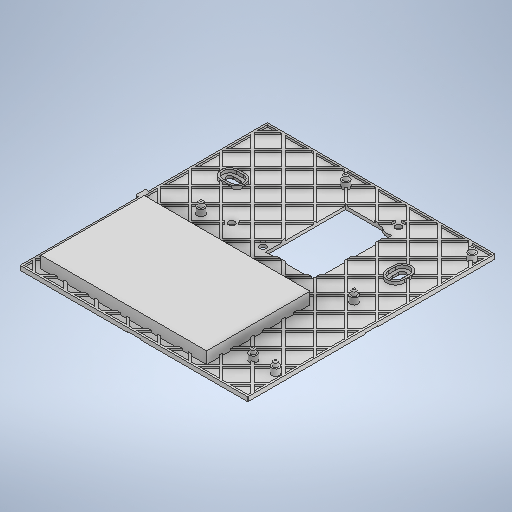
# Autodesk Inventor part: Back
Saved by Autodesk Inventor 2025.2 (Build 292293000, 293)
## iProperties
Created: 2026-06-16
Part Number: Back
Material: Generic
Document SubType Name: Modeling
Designer: Bruno
Density: 1 g/cm^3
Appearance: Default
Author: Bruno
## iProperties of the stored document Back_3DPrint.ipt
Created: 2026-06-25
Part Number: Back_3DPrint
Material: Generic
Document SubType Name: Modeling
Designer: Bruno
Density: 1 g/cm^3
Appearance: Default
Author: Bruno
Autodesk Inventor part; units mm, degrees
(part 1 of 2)
ref_plane "YZ Plane" through (0, 0, 0) normal (1, 0, 0) x (0, 1, 0)
ref_plane "XZ Plane" through (0, 0, 0) normal (0, 1, 0) x (-1, 0, 0)
ref_plane "XY Plane" through (0, 0, 0) normal (0, 0, 1) x (1, 0, 0)
sketch "Sketch1" plane through (0, 0, 0) normal (0, 1, 0) x (-1, 0, 0)
  line L0 (56.075, 35) -> (-60.725, 35) construction
  line L1 (-60.725, 35) -> (-60.725, -33.4)
  line L2 (-60.725, -33.4) -> (56.075, -33.4)
  line L3 (56.075, -33.4) -> (56.075, 35)
  line L4 (56.075, 35) -> (56.075, 93.4)
  line L5 (56.075, 93.4) -> (-60.725, 93.4)
  line L6 (-60.725, 93.4) -> (-60.725, 35)
  line L7 (20.8, 25.375) -> (-25.45, 25.375) construction
  line L8 (-25.45, 25.375) -> (-26.8, 24.025) construction
  line L9 (-26.8, 24.025) -> (-26.8, -24.025) construction
  line L10 (-26.8, -24.025) -> (-25.45, -25.375) construction
  line L11 (-25.45, -25.375) -> (20.8, -25.375) construction
  line L12 (20.8, -25.375) -> (26.8, -19.375) construction
  line L13 (26.8, -19.375) -> (26.8, 19.375) construction
  line L14 (26.8, 19.375) -> (20.8, 25.375) construction
  line L15 (0, 0) -> (14.4314, 0) construction
  line L16 (0, 0) -> (0, -16.3177) construction
  line L17 (20.8414, 25.475) -> (-25.4914, 25.475)
  line L18 (-25.4914, 25.475) -> (-26.9, 24.0664)
  line L19 (-26.9, 24.0664) -> (-26.9, -24.0664)
  line L20 (-26.9, -24.0664) -> (-25.4914, -25.475)
  line L21 (-25.4914, -25.475) -> (20.8414, -25.475)
  line L22 (20.8414, -25.475) -> (26.9, -19.4164)
  line L23 (26.9, -19.4164) -> (26.9, 19.4164) construction
  line L24 (26.9, 19.4164) -> (20.8414, 25.475)
  arc A0 (-26.9, -24.0664) -> (-25.4914, -25.475) centre (-25.4914, -24.0664) ccw
  arc A1 (-25.4914, 25.475) -> (-26.9, 24.0664) centre (-25.4914, 24.0664) ccw
  line L25 (29.5, -16.8716) -> (29.5, 16.8716)
  line L26 (26.9, -19.4164) -> (29.5, -16.8164)
  line L27 (26.9, 19.4164) -> (29.5, 16.8164)
  line L28 (-2.325, 0) -> (-2.325, -9.0577) construction
  line L29 (57.675, 95) -> (57.675, 33.4) construction
  line L30 (57.675, 33.4) -> (57.675, -35) construction
  line L31 (57.675, -35) -> (-62.325, -35) construction
  line L32 (-62.325, -35) -> (-62.325, 33.4) construction
  line L33 (-62.325, 33.4) -> (-62.325, 95) construction
  line L34 (-62.325, 95) -> (57.675, 95) construction
  line L35 (32.3911, 91.5) -> (-28.8133, 91.5) construction
  line L36 (-28.8133, 91.5) -> (-28.8133, 38.5) construction
  line L37 (-28.8133, 38.5) -> (32.3911, 38.5) construction
  line L38 (32.3911, 38.5) -> (32.3911, 91.5) construction
  line L39 (32.3911, 65) -> (-28.8133, 65) construction
  dimension "d57" = 6
  dimension "d0" = 116.8
  dimension "d6" = 50.75
  dimension "d7" = 53.6
  dimension "d8" = 50.75
  dimension "d9" = 53.6
  dimension "d10" = 45
  dimension "d11" = 48.05
  dimension "d12" = 38.75
  dimension "d13" = 0.1
  dimension "d19" = 2.7
  dimension "d166" = 24.475
  dimension "d167" = 1.6
  dimension "d168" = 70
  dimension "d169" = 53
  dimension "d170" = 60
  constraints: 80 end point, 13 perpendicular, 9 parallel, 4 horizontal, 4 point on circle, 4 vertical, 3 equal length, 2 centre point, 2 midpoint, 2 point on line, 2 tangent, 1 collinear, 1 horizontal alignment, 15 other
  measures "d0" distance of L1.end L2.end
  measures "d6" distance between parallel lines of L11 L7
  measures "d7" distance between parallel lines of L9 L13
  measures "d8" diameter of L7 L15
  measures "d9" diameter of L13 L16
  measures "d10" angle of L9 L10
  measures "d11" distance of L8.end L9.end
  measures "d12" distance of L12.end L13.end
  measures "d13" distance between parallel lines of L14 L24
  measures "d19" distance between parallel lines of L13 L25
  measures "d166" distance from line of L9 L28.start
  measures "d167" distance between parallel lines of L4 L29
  measures "d168" distance between parallel lines of L0 L31
  measures "d169" distance between parallel lines of L37 L35
  measures "d170" distance between parallel lines of L34 L0
extrude "Extrusion1" add sketch "Sketch1" along normal blind 1.6 contours L6 L5 L4 L3 L2 L1 | L18 A1 | L20 A0
sketch "Sketch2" plane through (0, 0, 0) normal (0, -1, 0) x (1, 0, 0)
  line L0 (60.725, -33.4) -> (-56.075, -33.4) projected
  line L1 (60.725, 93.4) -> (60.725, -33.4) projected
  line L2 (-56.075, 93.4) -> (60.725, 93.4) projected
  line L3 (-56.075, -33.4) -> (-56.075, 93.4) projected
  line L4 (-29.5, -16.8164) -> (-20.8414, -25.475) projected
  line L5 (-29.5, 16.8164) -> (-29.5, -16.8164) projected
  line L6 (-20.8414, 25.475) -> (-29.5, 16.8164) projected
  line L7 (25.4914, 25.475) -> (-20.8414, 25.475) projected
  line L8 (26.9, 24.0664) -> (25.4914, 25.475) projected
  line L9 (26.9, -24.0664) -> (26.9, 24.0664) projected
  line L10 (25.4914, -25.475) -> (26.9, -24.0664) projected
  line L11 (-20.8414, -25.475) -> (25.4914, -25.475) projected
  line L12 (-31.1, 17.4792) -> (-31.1, -17.4792)
  line L13 (-31.1, -17.4792) -> (-21.5042, -27.075)
  line L14 (-21.5042, -27.075) -> (26.1542, -27.075)
  line L15 (26.1542, -27.075) -> (28.5, -24.7292)
  line L16 (28.5, -24.7292) -> (28.5, 24.7292)
  line L17 (28.5, 24.7292) -> (26.1542, 27.075)
  line L18 (26.1542, 27.075) -> (-21.5042, 27.075)
  line L19 (-21.5042, 27.075) -> (-31.1, 17.4792)
  dimension "d20" = 1.6
  constraints: 16 end point, 7 other
  measures "d20" distance between parallel lines of L6 L19
extrude "Extrusion2" add sketch "Sketch2" along normal blind 25.235 contours L19 L18 L17 L16 L15 L14 L13 L12
sketch "Sketch3" plane through (0, -25.235, 0) normal (0, -1, 0) x (1, 0, 0)
  line L0 (-31.1, -17.4792) -> (-21.5042, -27.075) projected
  line L1 (-21.5042, -27.075) -> (26.1542, -27.075) projected
  line L2 (26.1542, -27.075) -> (28.5, -24.7292) projected
  line L3 (28.5, -24.7292) -> (28.5, 24.7292) projected
  line L4 (28.5, 24.7292) -> (26.1542, 27.075) projected
  line L5 (26.1542, 27.075) -> (-21.5042, 27.075) projected
  line L6 (-21.5042, 27.075) -> (-31.1, 17.4792) projected
  line L7 (-31.1, 17.4792) -> (-31.1, -17.4792) projected
  line L8 (-29.5, -16.8164) -> (-29.5, 16.8164) projected
  line L9 (-29.5, 16.8164) -> (-20.8414, 25.475) projected
  line L10 (-20.8414, 25.475) -> (25.4914, 25.475) projected
  line L11 (25.4914, 25.475) -> (26.9, 24.0664) projected
  line L12 (26.9, 24.0664) -> (26.9, -24.0664) projected
  line L13 (26.9, -24.0664) -> (25.4914, -25.475) projected
  line L14 (25.4914, -25.475) -> (-20.8414, -25.475) projected
  line L15 (-20.8414, -25.475) -> (-29.5, -16.8164) projected
  point P0 (0, 0)
extrude "Extrusion3" add sketch "Sketch3" along normal blind 1.6 contours L7 L6 L5 L4 L3 L2 L1 L0 | L8 L9 L10 L11 L12 L13 L14 L15
sketch "Sketch4" plane through (0, -26.835, 0) normal (0, -1, 0) x (1, 0, 0)
  line L0 (-21.5042, -27.075) -> (26.1542, -27.075) projected
  line L1 (26.1542, -27.075) -> (28.5, -24.7292) projected
  line L2 (28.5, -24.7292) -> (28.5, 24.7292) projected
  line L3 (28.5, 24.7292) -> (26.1542, 27.075) projected
  line L4 (26.1542, 27.075) -> (-21.5042, 27.075) projected
  line L5 (-21.5042, 27.075) -> (-31.1, 17.4792) projected
  line L6 (-31.1, 17.4792) -> (-31.1, -17.4792) projected
  line L7 (-31.1, -17.4792) -> (-21.5042, -27.075) projected
  line L8 (-31.1, 14.875) -> (-15.8, 14.875)
  line L9 (-15.8, 14.875) -> (-15.8, -0.775)
  line L10 (-15.8, -0.775) -> (-31.1, -0.775)
  line L11 (-29.5, -16.8164) -> (-29.5, 16.8164) projected
  line L12 (-29.5, 16.8164) -> (-20.8414, 25.475) projected
  line L13 (-20.8414, 25.475) -> (25.4914, 25.475) projected
  line L14 (25.4914, 25.475) -> (26.9, 24.0664) projected
  line L15 (26.9, 24.0664) -> (26.9, -24.0664) projected
  line L16 (26.9, -24.0664) -> (25.4914, -25.475) projected
  line L17 (25.4914, -25.475) -> (-20.8414, -25.475) projected
  line L18 (-20.8414, -25.475) -> (-29.5, -16.8164) projected
  point P0 (0, 0)
  dimension "d22" = 10.6
  dimension "d23" = 24.7
  dimension "d25" = 15.3
  constraints: 6 end point, 2 perpendicular, 2 point on line, 1 horizontal
  measures "d22" distance between parallel lines of L13 L8
  measures "d23" distance between parallel lines of L17 L10
  measures "d25" distance between parallel lines of L6 L9
extrude "Extrusion4" cut sketch "Sketch4" against normal blind 9 contours L6 L8 L11 L10 | L11 L8 L9 L10
sketch "Sketch5" plane through (0, -25.235, 0) normal (0, 1, 0) x (1, 0, 0)
  line L0 (-29.5, -16.8164) -> (-29.5, 16.8164) projected
  line L1 (-29.5, 16.8164) -> (-20.8414, 25.475) projected
  line L2 (-20.8414, -25.475) -> (-29.5, -16.8164) projected
  line L3 (25.4914, -25.475) -> (-20.8414, -25.475) projected
  line L4 (26.9, -24.0664) -> (25.4914, -25.475) projected
  line L5 (26.9, 24.0664) -> (26.9, -24.0664) projected
  line L6 (25.4914, 25.475) -> (26.9, 24.0664) projected
  line L7 (-20.8414, 25.475) -> (25.4914, 25.475) projected
  line L8 (-29.4, 16.775) -> (-29.4, -16.775) construction
  line L9 (-29.4, -16.775) -> (-20.8, -25.375) construction
  line L10 (-20.8, -25.375) -> (25.45, -25.375) construction
  line L11 (25.45, -25.375) -> (26.8, -24.025) construction
  line L12 (26.8, -24.025) -> (26.8, 24.025) construction
  line L13 (26.8, 24.025) -> (25.45, 25.375) construction
  line L14 (25.45, 25.375) -> (-20.8, 25.375) construction
  line L15 (-20.8, 25.375) -> (-29.4, 16.775) construction
  circle A0 centre (22.95, 21.625) radius 4.25
  circle A1 centre (22.95, 21.625) radius 2
  circle A2 centre (-3.05, -21.875) radius 3.8
  circle A3 centre (-3.05, -21.875) radius 2
  circle A4 centre (-21.55, -19.375) radius 4.25
  circle A5 centre (-21.55, -19.375) radius 2
  point P0 (0, 0)
  point P1 (21.15, 25.475)
  point P2 (26.9, 20.0566)
  point P3 (-1.8334, -25.475)
  point P4 (-4.2666, -25.475)
  point P5 (-22.9174, -23.399)
  point P6 (-25.574, -20.7424)
  dimension "d28" = 0.1
  dimension "d30" = 4
  dimension "d31" = 3.85
  dimension "d34" = 4
  dimension "d37" = 26
  dimension "d39" = 4
  dimension "d41" = 18.5
  dimension "d43" = 3.75
  dimension "d44" = 3.5
  dimension "d45" = 6
  dimension "d46" = 7.6
  dimension "d47" = 8.5
  dimension "d48" = 8.5
  constraints: 16 end point, 6 centre point, 3 coincident, 7 other
  measures "d28" distance between parallel lines of L0 L8
  measures "d30" diameter of A1
  measures "d31" distance from line of A0.centre L12
  measures "d34" diameter of A3
  measures "d37" horizontal distance of A0.centre A2.centre
  measures "d39" diameter of A5
  measures "d41" horizontal distance of A3.centre A4.centre
  measures "d43" distance from line of L14 A0.centre
  measures "d44" distance from line of L10 A2.centre
  measures "d45" distance from line of L10 A4.centre
  measures "d46" diameter of A2
  measures "d47" diameter of A0
  measures "d48" diameter of A4
extrude "Extrusion5" add sketch "Sketch5" along normal blind 20.015 contours A4 L2 | L7 A0 L5 | L7 L6 L5 A0 | A2 L3 picked at (-23.8461, -21.6142) picked at (-2.9696, -24.9368)
sketch "Sketch6" plane through (0, -25.235, 0) normal (0, 1, 0) x (1, 0, 0)
  circle A0 centre (-21.55, -19.375) radius 2 projected
  circle A1 centre (-3.05, -21.875) radius 2 projected
  circle A2 centre (22.95, 21.625) radius 2 projected
  point P0 (0, 0)
extrude "Extrusion6" add sketch "Sketch6" along normal blind 13.315
sketch "Sketch7" plane through (0, 1.6, 0) normal (0, 1, 0) x (1, 0, 0)
  line L0 (60.725, 33.4) -> (-56.075, 33.4) projected
  line L1 (-56.075, 33.4) -> (-56.075, -93.4) projected
  line L2 (-56.075, -93.4) -> (60.725, -93.4) projected
  line L3 (60.725, -93.4) -> (60.725, 33.4) projected
  line L4 (-29.5, 16.8164) -> (-20.8414, 25.475) projected
  line L5 (-20.8414, 25.475) -> (25.4914, 25.475) projected
  line L6 (25.4914, 25.475) -> (26.9, 24.0664) projected
  line L7 (26.9, 24.0664) -> (26.9, -24.0664) projected
  line L8 (26.9, -24.0664) -> (25.4914, -25.475) projected
  line L9 (25.4914, -25.475) -> (-20.8414, -25.475) projected
  line L10 (-20.8414, -25.475) -> (-29.5, -16.8164) projected
  line L11 (-29.5, -16.8164) -> (-29.5, 16.8164) projected
  circle A0 centre (-21.55, -19.375) radius 2 projected
  circle A1 centre (-3.05, -21.875) radius 2 projected
  circle A2 centre (22.95, 21.625) radius 2 projected
  circle A3 centre (-21.55, -19.375) radius 1.65
  circle A4 centre (-3.05, -21.875) radius 1.65
  circle A5 centre (22.95, 21.625) radius 1.65
  line L12 (-27.5, -15.988) -> (-20.013, -23.475)
  line L13 (-20.013, -23.475) -> (24.663, -23.475)
  line L14 (24.663, -23.475) -> (24.9, -23.238)
  line L15 (24.9, -23.238) -> (24.9, 23.238)
  line L16 (24.9, 23.238) -> (24.663, 23.475)
  line L17 (24.663, 23.475) -> (-20.013, 23.475)
  line L18 (-20.013, 23.475) -> (-27.5, 15.988)
  line L19 (-27.5, 15.988) -> (-27.5, -15.988)
  line L20 (-17.5277, -17.475) -> (-21.5, -13.5027)
  line L21 (-21.5, -13.5027) -> (-21.5, 13.5027)
  line L22 (-21.5, 13.5027) -> (-17.5277, 17.475)
  line L23 (-17.5277, 17.475) -> (18.9, 17.475)
  line L24 (18.9, 17.475) -> (18.9, -17.475)
  line L25 (18.9, -17.475) -> (-17.5277, -17.475)
  line L26 (21.15, 25.475) -> (-20.8414, 25.475) projected
  line L27 (0, 25.475) -> (0, -25.475)
  circle A6 centre (22.95, 21.625) radius 5.7987
  point P0 (0, 0)
  point P1 (0, 0)
  point P2 (22.1901, 23.475)
  point P3 (23.7099, 23.475)
  point P4 (24.9, 22.0694)
  point P5 (24.9, 21.1806)
  point P6 (24.9, 16.164)
  point P7 (0, -23.475)
  point P8 (0, 17.475)
  point P9 (-1.85, -23.475)
  point P10 (-4.25, -23.475)
  point P11 (-22.2334, -21.2546)
  point P12 (-23.4296, -20.0584)
  point P13 (-2.6469, -23.475)
  point P14 (-3.4531, -23.475)
  dimension "d53" = 3.3
  dimension "d54" = 3.3
  dimension "d55" = 3.3
  dimension "d56" = 2
  dimension "d57" = 6
  constraints: 30 end point, 5 coincident, 3 centre point, 2 point on line, 1 midpoint, 1 perpendicular, 15 other
  measures "d53" diameter of A3
  measures "d54" diameter of A4
  measures "d55" diameter of A5
  measures "d56" distance between parallel lines of L10 L12
  measures "d57" distance between parallel lines of L12 L20
extrude "Extrusion7" add sketch "Sketch7" against normal up to surface (1.6 mm away) contours L4 L5 L27 L17 L18 L19 L12 A0 L13 A1 L9 L10 L11 | L5 A6 L17 L27 | L5 L6 L7 A6 L15 A2 L16 L17 | L27 L23 L22 L21 L20 L25 L13 A1 L12 A0 L19 L18 L17 | L17 A6 L23 L27 | L27 L13 L14 L15 A6 L7 L8 L9 | L17 A2 L15 A6 | L27 L25 L20 L21 L22 L23 | L17 A2 L15 | A2 L17 | L13 A4 A1 | A1 L13 A4 | L17 L16 L15 A2 | L15 A2 | L12 A0 | A0 L12
sketch "Sketch8" plane through (0, 0, 0) normal (0, -1, 0) x (1, 0, 0)
  line L0 (-31.1, -17.4792) -> (-31.1, 17.4792) projected
  line L1 (-31.1, 17.4792) -> (-21.5042, 27.075) projected
  line L2 (-21.5042, 27.075) -> (26.1542, 27.075) projected
  line L3 (26.1542, 27.075) -> (28.5, 24.7292) projected
  line L4 (28.5, 24.7292) -> (28.5, -24.7292) projected
  line L5 (28.5, -24.7292) -> (26.1542, -27.075) projected
  line L6 (26.1542, -27.075) -> (-21.5042, -27.075) projected
  line L7 (-21.5042, -27.075) -> (-31.1, -17.4792) projected
  line L8 (60.725, -33.4) -> (-56.075, -33.4) projected
  line L9 (60.725, 93.4) -> (60.725, -33.4) projected
  line L10 (-56.075, 93.4) -> (60.725, 93.4) projected
  line L11 (-56.075, -33.4) -> (-56.075, 93.4) projected
  point P0 (0, 0)
extrude "Extrusion8" cut sketch "Sketch8" along normal through all contours L0 L1 L2 L3 L4 L5 L6 L7
sketch "Sketch15" plane through (0, 1.6, 0) normal (0, 1, 0) x (1, 0, 0)
  line L0 (26.8, -11.0928) -> (26.8, 9.4802) construction
  line L1 (-1.3136, 25.375) -> (13.9223, 25.375) construction
  circle A0 centre (56.325, 26) radius 1.2
  circle A1 centre (56.325, -74.75) radius 1.2
  circle A2 centre (44.825, -74.75) radius 1.2
  circle A3 centre (44.825, -23) radius 1.2
  circle A4 centre (-33.675, -23) radius 1.2
  circle A5 centre (-8.425, 26) radius 1.2
  point P0 (0, 0)
  dimension "d137" = 25.375
  dimension "d138" = 26.8
  dimension "d139" = 2.4
  dimension "d140" = 2.4
  dimension "d141" = 2.4
  dimension "d142" = 2.4
  dimension "d143" = 2.4
  dimension "d144" = 2.4
  dimension "d145" = 0.625
  dimension "d146" = 29.525
  dimension "d147" = 49
  dimension "d148" = 51.75
  dimension "d149" = 11.5
  dimension "d150" = 53.25
  dimension "d151" = 25.25
  constraints: 6 centre point, 4 end point, 3 horizontal alignment, 2 vertical alignment, 1 horizontal, 1 vertical
  measures "d137" distance from line of L1 point (0, 0)
  measures "d138" distance from line of point (0, 0) L0
  measures "d139" diameter of A2
  measures "d140" diameter of A1
  measures "d141" diameter of A3
  measures "d142" diameter of A0
  measures "d143" diameter of A4
  measures "d144" diameter of A5
  measures "d145" distance from line of L1 A0.centre
  measures "d146" distance from line of A0.centre L0
  measures "d147" vertical distance of A3.centre A0.centre
  measures "d148" distance of A2.centre A3.centre
  measures "d149" horizontal distance of A3.centre A0.centre
  measures "d150" horizontal distance of A5.centre A3.centre
  measures "d151" horizontal distance of A5.centre A4.centre
extrude "Extrusion12" add sketch "Sketch15" along normal blind 5.8
sketch "Sketch16" plane through (0, 1.6, 0) normal (0, 1, 0) x (1, 0, 0)
  circle A0 centre (-33.675, -23) radius 1.2 projected
  circle A1 centre (-8.425, 26) radius 1.2 projected
  circle A2 centre (56.325, 26) radius 1.2 projected
  circle A3 centre (44.825, -23) radius 1.2 projected
  circle A4 centre (44.825, -74.75) radius 1.2 projected
  circle A5 centre (56.325, -74.75) radius 1.2 projected
  circle A6 centre (56.325, -74.75) radius 2
  circle A7 centre (44.825, -74.75) radius 2
  circle A8 centre (56.325, 26) radius 2
  circle A9 centre (44.825, -23) radius 2
  circle A10 centre (-33.675, -23) radius 2
  circle A11 centre (-8.425, 26) radius 2
  point P0 (0, 0)
  dimension "d154" = 4
  dimension "d155" = 4
  dimension "d156" = 4
  dimension "d157" = 4
  dimension "d158" = 4
  dimension "d159" = 4
  constraints: 6 centre point, 6 coincident
  measures "d154" diameter of A6
  measures "d155" diameter of A7
  measures "d156" diameter of A9
  measures "d157" diameter of A8
  measures "d158" diameter of A11
  measures "d159" diameter of A10
extrude "Extrusion13" add sketch "Sketch16" along normal blind 3.2 contours A1 | A2 | A4 | A5 | A6 | A7 | A8 | A9 | A10 | A11
fillet "Fillet1" radius 0.6 6 edges at (55.125, 7.4, 74.75) (43.625, 7.4, 74.75) (55.125, 7.4, -26) (-9.625, 7.4, -26) (-34.875, 7.4, 23) (43.625, 7.4, 23)
sketch "Sketch18" plane through (0, 1.6, 0) normal (0, 1, 0) x (1, 0, 0)
  line L0 (-56.075, 33.4) -> (-56.075, -93.4) projected
  line L1 (60.725, -93.4) -> (60.725, 33.4) projected
  line L2 (-40.175, 0) -> (-56.075, 0) construction
  line L3 (44.825, 0) -> (60.725, 0) construction
  circle A0 centre (-40.175, 0) radius 1.75 construction
  circle A1 centre (-41.925, 0) radius 1.75
  circle A2 centre (-38.425, 0) radius 1.75
  circle A3 centre (44.825, 0) radius 1.75 construction
  line L4 (-38.425, -1.75) -> (-41.925, -1.75)
  line L5 (-38.425, 1.75) -> (-41.925, 1.75)
  circle A4 centre (44.825, -1.75) radius 1.75
  circle A5 centre (44.825, 1.75) radius 1.75
  line L6 (43.075, -1.75) -> (43.075, 1.75)
  line L7 (46.575, -1.75) -> (46.575, 1.75)
  point P0 (0, 0)
  dimension "d171" = 85
  dimension "d172" = 3.5
  dimension "d173" = 3.5
  constraints: 16 point on circle, 12 end point, 6 centre point, 4 tangent, 3 horizontal alignment, 3 point on line, 2 coincident, 2 perpendicular, 2 vertical, 2 vertical alignment, 1 collinear, 1 horizontal, 1 parallel
  measures "d171" distance of L2.start L3.start
  measures "d172" diameter of A0
  measures "d173" diameter of A3
extrude "Extrusion14" cut sketch "Sketch18" against normal through all
sketch "Sketch19" plane through (0, 1.6, 0) normal (0, 1, 0) x (1, 0, 0)
  arc A0 (-41.925, 1.75) -> (-41.925, -1.75) centre (-41.925, 0) ccw projected
  line L0 (-41.925, 1.75) -> (-38.425, 1.75) projected
  arc A1 (-38.425, -1.75) -> (-38.425, 1.75) centre (-38.425, 0) ccw projected
  line L1 (-38.425, -1.75) -> (-41.925, -1.75) projected
  line L2 (43.075, -1.75) -> (43.075, 1.75) projected
  arc A2 (46.575, 1.75) -> (43.075, 1.75) centre (44.825, 1.75) ccw projected
  line L3 (46.575, 1.75) -> (46.575, -1.75) projected
  arc A3 (43.075, -1.75) -> (46.575, -1.75) centre (44.825, -1.75) ccw projected
  circle A4 centre (44.825, -74.75) radius 2 projected
  circle A5 centre (-33.675, -23) radius 2 projected
  circle A6 centre (56.325, -74.75) radius 2 projected
  circle A7 centre (56.325, 26) radius 2 projected
  circle A8 centre (-8.425, 26) radius 2 projected
  circle A9 centre (44.825, -23) radius 2 projected
  line L4 (60.725, 33.4) -> (-56.075, 33.4) projected
  line L5 (-56.075, 33.4) -> (-56.075, -93.4) projected
  line L6 (-56.075, -93.4) -> (60.725, -93.4) projected
  line L7 (60.725, -93.4) -> (60.725, 33.4) projected
  circle A10 centre (-21.55, -19.375) radius 1.65 projected
  circle A11 centre (-3.05, -21.875) radius 1.65 projected
  arc A12 (18.9, 17.475) -> (24.9, 16.164) centre (22.95, 21.625) ccw projected
  line L8 (24.9, 16.164) -> (24.9, -23.238) projected
  line L9 (24.9, -23.238) -> (24.663, -23.475) projected
  line L10 (24.663, -23.475) -> (0, -23.475) projected
  line L11 (0, -23.475) -> (0, 17.475) projected
  line L12 (0, 17.475) -> (18.9, 17.475) projected
  circle A13 centre (22.95, 21.625) radius 1.65 projected
  line L13 (-38.425, 3.5) -> (-41.925, 3.5)
  arc A14 (-41.925, 3.5) -> (-41.925, -3.5) centre (-41.925, 0) ccw
  line L14 (-41.925, -3.5) -> (-38.425, -3.5)
  arc A15 (-38.425, -3.5) -> (-38.425, 3.5) centre (-38.425, 0) ccw
  line L15 (41.325, 1.75) -> (41.325, -1.75)
  arc A16 (41.325, -1.75) -> (48.325, -1.75) centre (44.825, -1.75) ccw
  line L16 (48.325, -1.75) -> (48.325, 1.75)
  arc A17 (48.325, 1.75) -> (41.325, 1.75) centre (44.825, 1.75) ccw
  line L17 (-41.925, 4.5) -> (-38.425, 4.5)
  arc A18 (-38.425, -4.5) -> (-38.425, 4.5) centre (-38.425, 0) ccw
  line L18 (-38.425, -4.5) -> (-41.925, -4.5)
  arc A19 (-41.925, 4.5) -> (-41.925, -4.5) centre (-41.925, 0) ccw
  line L19 (40.325, 1.75) -> (40.325, -1.75)
  arc A20 (40.325, -1.75) -> (49.325, -1.75) centre (44.825, -1.75) ccw
  line L20 (49.325, -1.75) -> (49.325, 1.75)
  arc A21 (49.325, 1.75) -> (40.325, 1.75) centre (44.825, 1.75) ccw
  point P0 (0, 0)
  dimension "d176" = 7
  dimension "d177" = 7
  dimension "d178" = 1
  dimension "d179" = 1
  constraints: 16 end point, 16 point on circle, 8 centre point, 12 other
  measures "d176" distance between parallel lines of L14 L13
  measures "d177" distance between parallel lines of L16 L15
  measures "d178" distance between parallel lines of L13 L17
  measures "d179" radial gap between concentric circles of A17 A21
extrude "Extrusion15" add sketch "Sketch19" along normal blind 1.6 contours L17 A18 L18 A19 | A21 L20 A20 L19
sketch "Sketch21" plane through (0, 1.6, 0) normal (0, 1, 0) x (1, 0, 0)
  line L0 (40.325, -1.75) -> (40.325, 1.75) projected
  arc A0 (49.325, 1.75) -> (40.325, 1.75) centre (44.825, 1.75) ccw projected
  line L1 (49.325, 1.75) -> (49.325, -1.75) projected
  arc A1 (40.325, -1.75) -> (49.325, -1.75) centre (44.825, -1.75) ccw projected
  arc A2 (-38.425, -4.5) -> (-38.425, 4.5) centre (-38.425, 0) ccw projected
  line L2 (-38.425, -4.5) -> (-41.925, -4.5) projected
  arc A3 (-41.925, 4.5) -> (-41.925, -4.5) centre (-41.925, 0) ccw projected
  line L3 (-41.925, 4.5) -> (-38.425, 4.5) projected
  circle A4 centre (44.825, -74.75) radius 2 projected
  circle A5 centre (-33.675, -23) radius 2 projected
  circle A6 centre (56.325, -74.75) radius 2 projected
  circle A7 centre (56.325, 26) radius 2 projected
  circle A8 centre (-8.425, 26) radius 2 projected
  circle A9 centre (44.825, -23) radius 2 projected
  line L4 (60.725, 33.4) -> (-56.075, 33.4) projected
  line L5 (-56.075, 33.4) -> (-56.075, -93.4) projected
  line L6 (-56.075, -93.4) -> (60.725, -93.4) projected
  line L7 (60.725, -93.4) -> (60.725, 33.4) projected
  circle A10 centre (-21.55, -19.375) radius 1.65 projected
  circle A11 centre (-3.05, -21.875) radius 1.65 projected
  arc A12 (18.9, 17.475) -> (24.9, 16.164) centre (22.95, 21.625) ccw projected
  line L8 (24.9, 16.164) -> (24.9, -23.238) projected
  line L9 (24.9, -23.238) -> (24.663, -23.475) projected
  line L10 (24.663, -23.475) -> (0, -23.475) projected
  line L11 (0, -23.475) -> (0, 17.475) projected
  line L12 (0, 17.475) -> (18.9, 17.475) projected
  circle A13 centre (22.95, 21.625) radius 1.65 projected
  line L13 (59.725, -92.4) -> (-55.075, -92.4)
  line L14 (-55.075, -92.4) -> (-55.075, 32.4)
  line L15 (-55.075, 32.4) -> (59.725, 32.4)
  line L16 (59.725, 32.4) -> (59.725, -92.4)
  line L17 (-47.9332, -95.0971) -> (-56.7721, -86.2582)
  line L18 (-56.7721, -86.2582) -> (-47.9332, -77.4194)
  line L19 (-47.9332, -77.4194) -> (-39.0944, -86.2582)
  line L20 (-39.0944, -86.2582) -> (-47.9332, -95.0971)
  line L21 (-47.9332, -79.1164) -> (-55.075, -86.2582)
  line L22 (-55.075, -86.2582) -> (-47.9332, -93.4)
  line L23 (-47.9332, -93.4) -> (-40.7914, -86.2582)
  line L24 (-40.7914, -86.2582) -> (-47.9332, -79.1164)
  line L25 (-56.075, -93.4) -> (-52.8526, -90.1776) construction
  line L26 (-47.0847, -78.2679) -> (-39.9429, -85.4097)
  line L27 (-39.9429, -85.4097) -> (-32.8011, -78.2679)
  line L28 (-39.9429, -71.1261) -> (-47.0847, -78.2679)
  line L29 (-32.8011, -78.2679) -> (-39.9429, -71.1261)
  line L30 (-39.0944, -70.2776) -> (-31.9526, -77.4194)
  line L31 (-31.9526, -77.4194) -> (-24.8108, -70.2776)
  line L32 (-31.9526, -63.1358) -> (-39.0944, -70.2776)
  line L33 (-24.8108, -70.2776) -> (-31.9526, -63.1358)
  line L34 (-31.1041, -62.2873) -> (-23.9623, -69.4291)
  line L35 (-23.9623, -69.4291) -> (-16.8205, -62.2873)
  line L36 (-23.9623, -55.1455) -> (-31.1041, -62.2873)
  line L37 (-16.8205, -62.2873) -> (-23.9623, -55.1455)
  line L38 (-23.1138, -54.297) -> (-15.972, -61.4388)
  line L39 (-15.972, -61.4388) -> (-8.8302, -54.297)
  line L40 (-15.972, -47.1552) -> (-23.1138, -54.297)
  line L41 (-8.8302, -54.297) -> (-15.972, -47.1552)
  line L42 (-15.1235, -46.3067) -> (-7.9817, -53.4485)
  line L43 (-7.9817, -53.4485) -> (-0.8399, -46.3067)
  line L44 (-7.9817, -39.1649) -> (-15.1235, -46.3067)
  line L45 (-0.8399, -46.3067) -> (-7.9817, -39.1649)
  line L46 (-7.1332, -38.3164) -> (0.0086, -45.4582)
  line L47 (0.0086, -45.4582) -> (7.1504, -38.3164)
  line L48 (0.0086, -31.1746) -> (-7.1332, -38.3164)
  line L49 (7.1504, -38.3164) -> (0.0086, -31.1746)
  line L50 (0.8571, -30.3261) -> (7.9989, -37.4679)
  line L51 (7.9989, -37.4679) -> (15.1407, -30.3261)
  line L52 (7.9989, -23.1843) -> (0.8571, -30.3261)
  line L53 (15.1407, -30.3261) -> (7.9989, -23.1843)
  line L54 (8.8475, -22.3358) -> (15.9892, -29.4775)
  line L55 (15.9892, -29.4775) -> (23.131, -22.3358)
  line L56 (15.9892, -15.194) -> (8.8475, -22.3358)
  line L57 (23.131, -22.3358) -> (15.9892, -15.194)
  line L58 (16.8378, -14.3455) -> (23.9795, -21.4872)
  line L59 (23.9795, -21.4872) -> (31.1213, -14.3455)
  line L60 (23.9795, -7.2037) -> (16.8378, -14.3455)
  line L61 (31.1213, -14.3455) -> (23.9795, -7.2037)
  line L62 (24.8281, -6.3552) -> (31.9698, -13.4969)
  line L63 (31.9698, -13.4969) -> (39.1116, -6.3552)
  line L64 (31.9698, 0.7866) -> (24.8281, -6.3552)
  line L65 (39.1116, -6.3552) -> (31.9698, 0.7866)
  line L66 (32.8184, 1.6352) -> (39.9602, -5.5066)
  line L67 (39.9602, -5.5066) -> (47.1019, 1.6352)
  line L68 (39.9602, 8.7769) -> (32.8184, 1.6352)
  line L69 (47.1019, 1.6352) -> (39.9602, 8.7769)
  line L70 (40.8087, 9.6255) -> (47.9505, 2.4837)
  line L71 (47.9505, 2.4837) -> (55.0922, 9.6255)
  line L72 (47.9505, 16.7672) -> (40.8087, 9.6255)
  line L73 (55.0922, 9.6255) -> (47.9505, 16.7672)
  line L74 (48.799, 17.6158) -> (55.9408, 10.474)
  line L75 (55.9408, 10.474) -> (63.0825, 17.6158)
  line L76 (55.9408, 24.7575) -> (48.799, 17.6158)
  line L77 (63.0825, 17.6158) -> (55.9408, 24.7575)
  line L78 (56.7893, 25.6061) -> (63.9311, 18.4643)
  line L79 (63.9311, 18.4643) -> (71.0728, 25.6061)
  line L80 (63.9311, 32.7478) -> (56.7893, 25.6061)
  line L81 (71.0728, 25.6061) -> (63.9311, 32.7478)
  line L82 (-47.0847, -94.2485) -> (-39.9429, -101.3903)
  line L83 (-39.9429, -101.3903) -> (-32.8011, -94.2485)
  line L84 (-39.9429, -87.1067) -> (-47.0847, -94.2485)
  line L85 (-32.8011, -94.2485) -> (-39.9429, -87.1067)
  line L86 (-39.0944, -86.2582) -> (-31.9526, -93.4)
  line L87 (-31.9526, -93.4) -> (-24.8108, -86.2582)
  line L88 (-31.9526, -79.1164) -> (-39.0944, -86.2582)
  line L89 (-24.8108, -86.2582) -> (-31.9526, -79.1164)
  line L90 (-31.1041, -78.2679) -> (-23.9623, -85.4097)
  line L91 (-23.9623, -85.4097) -> (-16.8205, -78.2679)
  line L92 (-23.9623, -71.1261) -> (-31.1041, -78.2679)
  line L93 (-16.8205, -78.2679) -> (-23.9623, -71.1261)
  line L94 (-23.1138, -70.2776) -> (-15.972, -77.4194)
  line L95 (-15.972, -77.4194) -> (-8.8302, -70.2776)
  line L96 (-15.972, -63.1358) -> (-23.1138, -70.2776)
  line L97 (-8.8302, -70.2776) -> (-15.972, -63.1358)
  line L98 (-15.1235, -62.2873) -> (-7.9817, -69.4291)
  line L99 (-7.9817, -69.4291) -> (-0.8399, -62.2873)
  line L100 (-7.9817, -55.1455) -> (-15.1235, -62.2873)
  line L101 (-0.8399, -62.2873) -> (-7.9817, -55.1455)
  line L102 (-7.1332, -54.297) -> (0.0086, -61.4388)
  line L103 (0.0086, -61.4388) -> (7.1504, -54.297)
  line L104 (0.0086, -47.1552) -> (-7.1332, -54.297)
  line L105 (7.1504, -54.297) -> (0.0086, -47.1552)
  line L106 (0.8571, -46.3067) -> (7.9989, -53.4485)
  line L107 (7.9989, -53.4485) -> (15.1407, -46.3067)
  line L108 (7.9989, -39.1649) -> (0.8571, -46.3067)
  line L109 (15.1407, -46.3067) -> (7.9989, -39.1649)
  line L110 (8.8475, -38.3164) -> (15.9892, -45.4582)
  line L111 (15.9892, -45.4582) -> (23.131, -38.3164)
  line L112 (15.9892, -31.1746) -> (8.8475, -38.3164)
  line L113 (23.131, -38.3164) -> (15.9892, -31.1746)
  line L114 (16.8378, -30.3261) -> (23.9795, -37.4679)
  line L115 (23.9795, -37.4679) -> (31.1213, -30.3261)
  line L116 (23.9795, -23.1843) -> (16.8378, -30.3261)
  line L117 (31.1213, -30.3261) -> (23.9795, -23.1843)
  line L118 (24.8281, -22.3358) -> (31.9698, -29.4775)
  line L119 (31.9698, -29.4775) -> (39.1116, -22.3358)
  line L120 (31.9698, -15.194) -> (24.8281, -22.3358)
  line L121 (39.1116, -22.3358) -> (31.9698, -15.194)
  line L122 (32.8184, -14.3455) -> (39.9602, -21.4872)
  line L123 (39.9602, -21.4872) -> (47.1019, -14.3455)
  line L124 (39.9602, -7.2037) -> (32.8184, -14.3455)
  line L125 (47.1019, -14.3455) -> (39.9602, -7.2037)
  line L126 (40.8087, -6.3552) -> (47.9505, -13.4969)
  line L127 (47.9505, -13.4969) -> (55.0922, -6.3552)
  line L128 (47.9505, 0.7866) -> (40.8087, -6.3552)
  line L129 (55.0922, -6.3552) -> (47.9505, 0.7866)
  line L130 (48.799, 1.6352) -> (55.9408, -5.5066)
  line L131 (55.9408, -5.5066) -> (63.0825, 1.6352)
  line L132 (55.9408, 8.7769) -> (48.799, 1.6352)
  line L133 (63.0825, 1.6352) -> (55.9408, 8.7769)
  line L134 (56.7893, 9.6255) -> (63.9311, 2.4837)
  line L135 (63.9311, 2.4837) -> (71.0728, 9.6255)
  line L136 (63.9311, 16.7672) -> (56.7893, 9.6255)
  line L137 (71.0728, 9.6255) -> (63.9311, 16.7672)
  line L138 (64.7796, 17.6158) -> (71.9214, 10.474)
  line L139 (71.9214, 10.474) -> (79.0632, 17.6158)
  line L140 (71.9214, 24.7575) -> (64.7796, 17.6158)
  line L141 (79.0632, 17.6158) -> (71.9214, 24.7575)
  line L142 (-63.0653, -78.2679) -> (-55.9235, -85.4097)
  line L143 (-55.9235, -85.4097) -> (-48.7817, -78.2679)
  line L144 (-55.9235, -71.1261) -> (-63.0653, -78.2679)
  line L145 (-48.7817, -78.2679) -> (-55.9235, -71.1261)
  line L146 (-55.075, -70.2776) -> (-47.9332, -77.4194)
  line L147 (-47.9332, -77.4194) -> (-40.7914, -70.2776)
  line L148 (-47.9332, -63.1358) -> (-55.075, -70.2776)
  line L149 (-40.7914, -70.2776) -> (-47.9332, -63.1358)
  line L150 (-47.0847, -62.2873) -> (-39.9429, -69.4291)
  line L151 (-39.9429, -69.4291) -> (-32.8011, -62.2873)
  line L152 (-39.9429, -55.1455) -> (-47.0847, -62.2873)
  line L153 (-32.8011, -62.2873) -> (-39.9429, -55.1455)
  line L154 (-39.0944, -54.297) -> (-31.9526, -61.4388)
  line L155 (-31.9526, -61.4388) -> (-24.8108, -54.297)
  line L156 (-31.9526, -47.1552) -> (-39.0944, -54.297)
  line L157 (-24.8108, -54.297) -> (-31.9526, -47.1552)
  line L158 (-31.1041, -46.3067) -> (-23.9623, -53.4485)
  line L159 (-23.9623, -53.4485) -> (-16.8205, -46.3067)
  line L160 (-23.9623, -39.1649) -> (-31.1041, -46.3067)
  line L161 (-16.8205, -46.3067) -> (-23.9623, -39.1649)
  line L162 (-23.1138, -38.3164) -> (-15.972, -45.4582)
  line L163 (-15.972, -45.4582) -> (-8.8302, -38.3164)
  line L164 (-15.972, -31.1746) -> (-23.1138, -38.3164)
  line L165 (-8.8302, -38.3164) -> (-15.972, -31.1746)
  line L166 (-15.1235, -30.3261) -> (-7.9817, -37.4679)
  line L167 (-7.9817, -37.4679) -> (-0.8399, -30.3261)
  line L168 (-7.9817, -23.1843) -> (-15.1235, -30.3261)
  line L169 (-0.8399, -30.3261) -> (-7.9817, -23.1843)
  line L170 (-7.1332, -22.3358) -> (0.0086, -29.4775)
  line L171 (0.0086, -29.4775) -> (7.1504, -22.3358)
  line L172 (0.0086, -15.194) -> (-7.1332, -22.3358)
  line L173 (7.1504, -22.3358) -> (0.0086, -15.194)
  line L174 (0.8571, -14.3455) -> (7.9989, -21.4872)
  line L175 (7.9989, -21.4872) -> (15.1407, -14.3455)
  line L176 (7.9989, -7.2037) -> (0.8571, -14.3455)
  line L177 (15.1407, -14.3455) -> (7.9989, -7.2037)
  line L178 (8.8475, -6.3552) -> (15.9892, -13.4969)
  line L179 (15.9892, -13.4969) -> (23.131, -6.3552)
  line L180 (15.9892, 0.7866) -> (8.8475, -6.3552)
  line L181 (23.131, -6.3552) -> (15.9892, 0.7866)
  line L182 (16.8378, 1.6352) -> (23.9795, -5.5066)
  line L183 (23.9795, -5.5066) -> (31.1213, 1.6352)
  line L184 (23.9795, 8.7769) -> (16.8378, 1.6352)
  line L185 (31.1213, 1.6352) -> (23.9795, 8.7769)
  line L186 (24.8281, 9.6255) -> (31.9698, 2.4837)
  line L187 (31.9698, 2.4837) -> (39.1116, 9.6255)
  line L188 (31.9698, 16.7672) -> (24.8281, 9.6255)
  line L189 (39.1116, 9.6255) -> (31.9698, 16.7672)
  line L190 (32.8184, 17.6158) -> (39.9602, 10.474)
  line L191 (39.9602, 10.474) -> (47.1019, 17.6158)
  line L192 (39.9602, 24.7575) -> (32.8184, 17.6158)
  line L193 (47.1019, 17.6158) -> (39.9602, 24.7575)
  line L194 (40.8087, 25.6061) -> (47.9505, 18.4643)
  line L195 (47.9505, 18.4643) -> (55.0922, 25.6061)
  line L196 (47.9505, 32.7478) -> (40.8087, 25.6061)
  line L197 (55.0922, 25.6061) -> (47.9505, 32.7478)
  line L198 (48.799, 33.5964) -> (55.9408, 26.4546)
  line L199 (55.9408, 26.4546) -> (63.0825, 33.5964)
  line L200 (55.9408, 40.7382) -> (48.799, 33.5964)
  line L201 (63.0825, 33.5964) -> (55.9408, 40.7382)
  line L202 (-39.0944, -102.2388) -> (-31.9526, -109.3806)
  line L203 (-31.9526, -109.3806) -> (-24.8108, -102.2388)
  line L204 (-31.9526, -95.0971) -> (-39.0944, -102.2388)
  line L205 (-24.8108, -102.2388) -> (-31.9526, -95.0971)
  line L206 (-31.1041, -94.2485) -> (-23.9623, -101.3903)
  line L207 (-23.9623, -101.3903) -> (-16.8205, -94.2485)
  line L208 (-23.9623, -87.1067) -> (-31.1041, -94.2485)
  line L209 (-16.8205, -94.2485) -> (-23.9623, -87.1067)
  line L210 (-23.1138, -86.2582) -> (-15.972, -93.4)
  line L211 (-15.972, -93.4) -> (-8.8302, -86.2582)
  line L212 (-15.972, -79.1164) -> (-23.1138, -86.2582)
  line L213 (-8.8302, -86.2582) -> (-15.972, -79.1164)
  line L214 (-15.1235, -78.2679) -> (-7.9817, -85.4097)
  line L215 (-7.9817, -85.4097) -> (-0.8399, -78.2679)
  line L216 (-7.9817, -71.1261) -> (-15.1235, -78.2679)
  line L217 (-0.8399, -78.2679) -> (-7.9817, -71.1261)
  line L218 (-7.1332, -70.2776) -> (0.0086, -77.4194)
  line L219 (0.0086, -77.4194) -> (7.1504, -70.2776)
  line L220 (0.0086, -63.1358) -> (-7.1332, -70.2776)
  line L221 (7.1504, -70.2776) -> (0.0086, -63.1358)
  line L222 (0.8571, -62.2873) -> (7.9989, -69.4291)
  line L223 (7.9989, -69.4291) -> (15.1407, -62.2873)
  line L224 (7.9989, -55.1455) -> (0.8571, -62.2873)
  line L225 (15.1407, -62.2873) -> (7.9989, -55.1455)
  line L226 (8.8475, -54.297) -> (15.9892, -61.4388)
  line L227 (15.9892, -61.4388) -> (23.131, -54.297)
  line L228 (15.9892, -47.1552) -> (8.8475, -54.297)
  line L229 (23.131, -54.297) -> (15.9892, -47.1552)
  line L230 (16.8378, -46.3067) -> (23.9795, -53.4485)
  line L231 (23.9795, -53.4485) -> (31.1213, -46.3067)
  line L232 (23.9795, -39.1649) -> (16.8378, -46.3067)
  line L233 (31.1213, -46.3067) -> (23.9795, -39.1649)
  line L234 (24.8281, -38.3164) -> (31.9698, -45.4582)
  line L235 (31.9698, -45.4582) -> (39.1116, -38.3164)
  line L236 (31.9698, -31.1746) -> (24.8281, -38.3164)
  line L237 (39.1116, -38.3164) -> (31.9698, -31.1746)
  line L238 (32.8184, -30.3261) -> (39.9602, -37.4679)
  line L239 (39.9602, -37.4679) -> (47.1019, -30.3261)
  line L240 (39.9602, -23.1843) -> (32.8184, -30.3261)
  line L241 (47.1019, -30.3261) -> (39.9602, -23.1843)
  line L242 (40.8087, -22.3358) -> (47.9505, -29.4775)
  line L243 (47.9505, -29.4775) -> (55.0922, -22.3358)
  line L244 (47.9505, -15.194) -> (40.8087, -22.3358)
  line L245 (55.0922, -22.3358) -> (47.9505, -15.194)
  line L246 (48.799, -14.3455) -> (55.9408, -21.4872)
  line L247 (55.9408, -21.4872) -> (63.0825, -14.3455)
  line L248 (55.9408, -7.2037) -> (48.799, -14.3455)
  line L249 (63.0825, -14.3455) -> (55.9408, -7.2037)
  line L250 (56.7893, -6.3552) -> (63.9311, -13.4969)
  line L251 (63.9311, -13.4969) -> (71.0728, -6.3552)
  line L252 (63.9311, 0.7866) -> (56.7893, -6.3552)
  line L253 (71.0728, -6.3552) -> (63.9311, 0.7866)
  line L254 (64.7796, 1.6352) -> (71.9214, -5.5066)
  line L255 (71.9214, -5.5066) -> (79.0632, 1.6352)
  line L256 (71.9214, 8.7769) -> (64.7796, 1.6352)
  line L257 (79.0632, 1.6352) -> (71.9214, 8.7769)
  line L258 (72.7699, 9.6255) -> (79.9117, 2.4837)
  line L259 (79.9117, 2.4837) -> (87.0535, 9.6255)
  line L260 (79.9117, 16.7672) -> (72.7699, 9.6255)
  line L261 (87.0535, 9.6255) -> (79.9117, 16.7672)
  line L262 (-71.0556, -70.2776) -> (-63.9138, -77.4194)
  line L263 (-63.9138, -77.4194) -> (-56.7721, -70.2776)
  line L264 (-63.9138, -63.1358) -> (-71.0556, -70.2776)
  line L265 (-56.7721, -70.2776) -> (-63.9138, -63.1358)
  line L266 (-63.0653, -62.2873) -> (-55.9235, -69.4291)
  line L267 (-55.9235, -69.4291) -> (-48.7817, -62.2873)
  line L268 (-55.9235, -55.1455) -> (-63.0653, -62.2873)
  line L269 (-48.7817, -62.2873) -> (-55.9235, -55.1455)
  line L270 (-55.075, -54.297) -> (-47.9332, -61.4388)
  line L271 (-47.9332, -61.4388) -> (-40.7914, -54.297)
  line L272 (-47.9332, -47.1552) -> (-55.075, -54.297)
  line L273 (-40.7914, -54.297) -> (-47.9332, -47.1552)
  line L274 (-47.0847, -46.3067) -> (-39.9429, -53.4485)
  line L275 (-39.9429, -53.4485) -> (-32.8011, -46.3067)
  line L276 (-39.9429, -39.1649) -> (-47.0847, -46.3067)
  line L277 (-32.8011, -46.3067) -> (-39.9429, -39.1649)
  line L278 (-39.0944, -38.3164) -> (-31.9526, -45.4582)
  line L279 (-31.9526, -45.4582) -> (-24.8108, -38.3164)
  line L280 (-31.9526, -31.1746) -> (-39.0944, -38.3164)
  line L281 (-24.8108, -38.3164) -> (-31.9526, -31.1746)
  line L282 (-31.1041, -30.3261) -> (-23.9623, -37.4679)
  line L283 (-23.9623, -37.4679) -> (-16.8205, -30.3261)
  line L284 (-23.9623, -23.1843) -> (-31.1041, -30.3261)
  line L285 (-16.8205, -30.3261) -> (-23.9623, -23.1843)
  line L286 (-23.1138, -22.3358) -> (-15.972, -29.4775)
  line L287 (-15.972, -29.4775) -> (-8.8302, -22.3358)
  line L288 (-15.972, -15.194) -> (-23.1138, -22.3358)
  line L289 (-8.8302, -22.3358) -> (-15.972, -15.194)
  line L290 (-15.1235, -14.3455) -> (-7.9817, -21.4872)
  line L291 (-7.9817, -21.4872) -> (-0.8399, -14.3455)
  line L292 (-7.9817, -7.2037) -> (-15.1235, -14.3455)
  line L293 (-0.8399, -14.3455) -> (-7.9817, -7.2037)
  line L294 (-7.1332, -6.3552) -> (0.0086, -13.4969)
  line L295 (0.0086, -13.4969) -> (7.1504, -6.3552)
  line L296 (0.0086, 0.7866) -> (-7.1332, -6.3552)
  line L297 (7.1504, -6.3552) -> (0.0086, 0.7866)
  line L298 (0.8571, 1.6352) -> (7.9989, -5.5066)
  line L299 (7.9989, -5.5066) -> (15.1407, 1.6352)
  line L300 (7.9989, 8.7769) -> (0.8571, 1.6352)
  line L301 (15.1407, 1.6352) -> (7.9989, 8.7769)
  line L302 (8.8475, 9.6255) -> (15.9892, 2.4837)
  line L303 (15.9892, 2.4837) -> (23.131, 9.6255)
  line L304 (15.9892, 16.7672) -> (8.8475, 9.6255)
  line L305 (23.131, 9.6255) -> (15.9892, 16.7672)
  line L306 (16.8378, 17.6158) -> (23.9795, 10.474)
  line L307 (23.9795, 10.474) -> (31.1213, 17.6158)
  line L308 (23.9795, 24.7575) -> (16.8378, 17.6158)
  line L309 (31.1213, 17.6158) -> (23.9795, 24.7575)
  line L310 (24.8281, 25.6061) -> (31.9698, 18.4643)
  line L311 (31.9698, 18.4643) -> (39.1116, 25.6061)
  line L312 (31.9698, 32.7478) -> (24.8281, 25.6061)
  line L313 (39.1116, 25.6061) -> (31.9698, 32.7478)
  line L314 (32.8184, 33.5964) -> (39.9602, 26.4546)
  line L315 (39.9602, 26.4546) -> (47.1019, 33.5964)
  line L316 (39.9602, 40.7382) -> (32.8184, 33.5964)
  line L317 (47.1019, 33.5964) -> (39.9602, 40.7382)
  line L318 (40.8087, 41.5867) -> (47.9505, 34.4449)
  line L319 (47.9505, 34.4449) -> (55.0922, 41.5867)
  line L320 (47.9505, 48.7285) -> (40.8087, 41.5867)
  line L321 (55.0922, 41.5867) -> (47.9505, 48.7285)
  line L322 (-31.1041, -110.2291) -> (-23.9623, -117.3709)
  line L323 (-23.9623, -117.3709) -> (-16.8205, -110.2291)
  line L324 (-23.9623, -103.0874) -> (-31.1041, -110.2291)
  line L325 (-16.8205, -110.2291) -> (-23.9623, -103.0874)
  line L326 (-23.1138, -102.2388) -> (-15.972, -109.3806)
  line L327 (-15.972, -109.3806) -> (-8.8302, -102.2388)
  line L328 (-15.972, -95.0971) -> (-23.1138, -102.2388)
  line L329 (-8.8302, -102.2388) -> (-15.972, -95.0971)
  line L330 (-15.1235, -94.2485) -> (-7.9817, -101.3903)
  line L331 (-7.9817, -101.3903) -> (-0.8399, -94.2485)
  line L332 (-7.9817, -87.1067) -> (-15.1235, -94.2485)
  line L333 (-0.8399, -94.2485) -> (-7.9817, -87.1067)
  line L334 (-7.1332, -86.2582) -> (0.0086, -93.4)
  line L335 (0.0086, -93.4) -> (7.1504, -86.2582)
  line L336 (0.0086, -79.1164) -> (-7.1332, -86.2582)
  line L337 (7.1504, -86.2582) -> (0.0086, -79.1164)
  line L338 (0.8571, -78.2679) -> (7.9989, -85.4097)
  line L339 (7.9989, -85.4097) -> (15.1407, -78.2679)
  line L340 (7.9989, -71.1261) -> (0.8571, -78.2679)
  line L341 (15.1407, -78.2679) -> (7.9989, -71.1261)
  line L342 (8.8475, -70.2776) -> (15.9892, -77.4194)
  line L343 (15.9892, -77.4194) -> (23.131, -70.2776)
  line L344 (15.9892, -63.1358) -> (8.8475, -70.2776)
  line L345 (23.131, -70.2776) -> (15.9892, -63.1358)
  line L346 (16.8378, -62.2873) -> (23.9795, -69.4291)
  line L347 (23.9795, -69.4291) -> (31.1213, -62.2873)
  line L348 (23.9795, -55.1455) -> (16.8378, -62.2873)
  line L349 (31.1213, -62.2873) -> (23.9795, -55.1455)
  line L350 (24.8281, -54.297) -> (31.9698, -61.4388)
  line L351 (31.9698, -61.4388) -> (39.1116, -54.297)
  line L352 (31.9698, -47.1552) -> (24.8281, -54.297)
  line L353 (39.1116, -54.297) -> (31.9698, -47.1552)
  line L354 (32.8184, -46.3067) -> (39.9602, -53.4485)
  line L355 (39.9602, -53.4485) -> (47.1019, -46.3067)
  line L356 (39.9602, -39.1649) -> (32.8184, -46.3067)
  line L357 (47.1019, -46.3067) -> (39.9602, -39.1649)
  line L358 (40.8087, -38.3164) -> (47.9505, -45.4582)
  line L359 (47.9505, -45.4582) -> (55.0922, -38.3164)
  line L360 (47.9505, -31.1746) -> (40.8087, -38.3164)
  line L361 (55.0922, -38.3164) -> (47.9505, -31.1746)
  line L362 (48.799, -30.3261) -> (55.9408, -37.4679)
  line L363 (55.9408, -37.4679) -> (63.0825, -30.3261)
  line L364 (55.9408, -23.1843) -> (48.799, -30.3261)
  line L365 (63.0825, -30.3261) -> (55.9408, -23.1843)
  line L366 (56.7893, -22.3358) -> (63.9311, -29.4775)
  line L367 (63.9311, -29.4775) -> (71.0728, -22.3358)
  line L368 (63.9311, -15.194) -> (56.7893, -22.3358)
  line L369 (71.0728, -22.3358) -> (63.9311, -15.194)
  line L370 (64.7796, -14.3455) -> (71.9214, -21.4872)
  line L371 (71.9214, -21.4872) -> (79.0632, -14.3455)
  line L372 (71.9214, -7.2037) -> (64.7796, -14.3455)
  line L373 (79.0632, -14.3455) -> (71.9214, -7.2037)
  line L374 (72.7699, -6.3552) -> (79.9117, -13.4969)
  line L375 (79.9117, -13.4969) -> (87.0535, -6.3552)
  line L376 (79.9117, 0.7866) -> (72.7699, -6.3552)
  line L377 (87.0535, -6.3552) -> (79.9117, 0.7866)
  line L378 (80.7602, 1.6352) -> (87.902, -5.5066)
  line L379 (87.902, -5.5066) -> (95.0438, 1.6352)
  line L380 (87.902, 8.7769) -> (80.7602, 1.6352)
  line L381 (95.0438, 1.6352) -> (87.902, 8.7769)
  line L382 (-79.0459, -62.2873) -> (-71.9041, -69.4291)
  line L383 (-71.9041, -69.4291) -> (-64.7624, -62.2873)
  line L384 (-71.9041, -55.1455) -> (-79.0459, -62.2873)
  line L385 (-64.7624, -62.2873) -> (-71.9041, -55.1455)
  line L386 (-71.0556, -54.297) -> (-63.9138, -61.4388)
  line L387 (-63.9138, -61.4388) -> (-56.7721, -54.297)
  line L388 (-63.9138, -47.1552) -> (-71.0556, -54.297)
  line L389 (-56.7721, -54.297) -> (-63.9138, -47.1552)
  line L390 (-63.0653, -46.3067) -> (-55.9235, -53.4485)
  line L391 (-55.9235, -53.4485) -> (-48.7817, -46.3067)
  line L392 (-55.9235, -39.1649) -> (-63.0653, -46.3067)
  line L393 (-48.7817, -46.3067) -> (-55.9235, -39.1649)
  line L394 (-55.075, -38.3164) -> (-47.9332, -45.4582)
  line L395 (-47.9332, -45.4582) -> (-40.7914, -38.3164)
  line L396 (-47.9332, -31.1746) -> (-55.075, -38.3164)
  line L397 (-40.7914, -38.3164) -> (-47.9332, -31.1746)
  line L398 (-47.0847, -30.3261) -> (-39.9429, -37.4679)
  line L399 (-39.9429, -37.4679) -> (-32.8011, -30.3261)
  line L400 (-39.9429, -23.1843) -> (-47.0847, -30.3261)
  line L401 (-32.8011, -30.3261) -> (-39.9429, -23.1843)
  line L402 (-39.0944, -22.3358) -> (-31.9526, -29.4775)
  line L403 (-31.9526, -29.4775) -> (-24.8108, -22.3358)
  line L404 (-31.9526, -15.194) -> (-39.0944, -22.3358)
  line L405 (-24.8108, -22.3358) -> (-31.9526, -15.194)
  line L406 (-31.1041, -14.3455) -> (-23.9623, -21.4872)
  line L407 (-23.9623, -21.4872) -> (-16.8205, -14.3455)
  line L408 (-23.9623, -7.2037) -> (-31.1041, -14.3455)
  line L409 (-16.8205, -14.3455) -> (-23.9623, -7.2037)
  line L410 (-23.1138, -6.3552) -> (-15.972, -13.4969)
  line L411 (-15.972, -13.4969) -> (-8.8302, -6.3552)
  line L412 (-15.972, 0.7866) -> (-23.1138, -6.3552)
  line L413 (-8.8302, -6.3552) -> (-15.972, 0.7866)
  line L414 (-15.1235, 1.6352) -> (-7.9817, -5.5066)
  line L415 (-7.9817, -5.5066) -> (-0.8399, 1.6352)
  line L416 (-7.9817, 8.7769) -> (-15.1235, 1.6352)
  line L417 (-0.8399, 1.6352) -> (-7.9817, 8.7769)
  line L418 (-7.1332, 9.6255) -> (0.0086, 2.4837)
  line L419 (0.0086, 2.4837) -> (7.1504, 9.6255)
  line L420 (0.0086, 16.7672) -> (-7.1332, 9.6255)
  line L421 (7.1504, 9.6255) -> (0.0086, 16.7672)
  line L422 (0.8571, 17.6158) -> (7.9989, 10.474)
  line L423 (7.9989, 10.474) -> (15.1407, 17.6158)
  line L424 (7.9989, 24.7575) -> (0.8571, 17.6158)
  line L425 (15.1407, 17.6158) -> (7.9989, 24.7575)
  line L426 (8.8475, 25.6061) -> (15.9892, 18.4643)
  line L427 (15.9892, 18.4643) -> (23.131, 25.6061)
  line L428 (15.9892, 32.7478) -> (8.8475, 25.6061)
  line L429 (23.131, 25.6061) -> (15.9892, 32.7478)
  line L430 (16.8378, 33.5964) -> (23.9795, 26.4546)
  line L431 (23.9795, 26.4546) -> (31.1213, 33.5964)
  line L432 (23.9795, 40.7382) -> (16.8378, 33.5964)
  line L433 (31.1213, 33.5964) -> (23.9795, 40.7382)
  line L434 (24.8281, 41.5867) -> (31.9698, 34.4449)
  line L435 (31.9698, 34.4449) -> (39.1116, 41.5867)
  line L436 (31.9698, 48.7285) -> (24.8281, 41.5867)
  line L437 (39.1116, 41.5867) -> (31.9698, 48.7285)
  line L438 (32.8184, 49.577) -> (39.9602, 42.4352)
  line L439 (39.9602, 42.4352) -> (47.1019, 49.577)
  line L440 (39.9602, 56.7188) -> (32.8184, 49.577)
  line L441 (47.1019, 49.577) -> (39.9602, 56.7188)
  line L442 (-23.1138, -118.2194) -> (-15.972, -125.3612)
  line L443 (-15.972, -125.3612) -> (-8.8302, -118.2194)
  line L444 (-15.972, -111.0777) -> (-23.1138, -118.2194)
  line L445 (-8.8302, -118.2194) -> (-15.972, -111.0777)
  line L446 (-15.1235, -110.2291) -> (-7.9817, -117.3709)
  line L447 (-7.9817, -117.3709) -> (-0.8399, -110.2291)
  line L448 (-7.9817, -103.0874) -> (-15.1235, -110.2291)
  line L449 (-0.8399, -110.2291) -> (-7.9817, -103.0874)
  line L450 (-7.1332, -102.2388) -> (0.0086, -109.3806)
  line L451 (0.0086, -109.3806) -> (7.1504, -102.2388)
  line L452 (0.0086, -95.0971) -> (-7.1332, -102.2388)
  line L453 (7.1504, -102.2388) -> (0.0086, -95.0971)
  line L454 (0.8571, -94.2485) -> (7.9989, -101.3903)
  line L455 (7.9989, -101.3903) -> (15.1407, -94.2485)
  line L456 (7.9989, -87.1067) -> (0.8571, -94.2485)
  line L457 (15.1407, -94.2485) -> (7.9989, -87.1067)
  line L458 (8.8475, -86.2582) -> (15.9892, -93.4)
  line L459 (15.9892, -93.4) -> (23.131, -86.2582)
  line L460 (15.9892, -79.1164) -> (8.8475, -86.2582)
  line L461 (23.131, -86.2582) -> (15.9892, -79.1164)
  line L462 (16.8378, -78.2679) -> (23.9795, -85.4097)
  line L463 (23.9795, -85.4097) -> (31.1213, -78.2679)
  line L464 (23.9795, -71.1261) -> (16.8378, -78.2679)
  line L465 (31.1213, -78.2679) -> (23.9795, -71.1261)
  line L466 (24.8281, -70.2776) -> (31.9698, -77.4194)
  line L467 (31.9698, -77.4194) -> (39.1116, -70.2776)
  line L468 (31.9698, -63.1358) -> (24.8281, -70.2776)
  line L469 (39.1116, -70.2776) -> (31.9698, -63.1358)
  line L470 (32.8184, -62.2873) -> (39.9602, -69.4291)
  line L471 (39.9602, -69.4291) -> (47.1019, -62.2873)
  line L472 (39.9602, -55.1455) -> (32.8184, -62.2873)
  line L473 (47.1019, -62.2873) -> (39.9602, -55.1455)
  line L474 (40.8087, -54.297) -> (47.9505, -61.4388)
  line L475 (47.9505, -61.4388) -> (55.0922, -54.297)
  line L476 (47.9505, -47.1552) -> (40.8087, -54.297)
  line L477 (55.0922, -54.297) -> (47.9505, -47.1552)
  line L478 (48.799, -46.3067) -> (55.9408, -53.4485)
  line L479 (55.9408, -53.4485) -> (63.0825, -46.3067)
  line L480 (55.9408, -39.1649) -> (48.799, -46.3067)
  line L481 (63.0825, -46.3067) -> (55.9408, -39.1649)
  line L482 (56.7893, -38.3164) -> (63.9311, -45.4582)
  line L483 (63.9311, -45.4582) -> (71.0728, -38.3164)
  line L484 (63.9311, -31.1746) -> (56.7893, -38.3164)
  line L485 (71.0728, -38.3164) -> (63.9311, -31.1746)
  line L486 (64.7796, -30.3261) -> (71.9214, -37.4679)
  line L487 (71.9214, -37.4679) -> (79.0632, -30.3261)
  line L488 (71.9214, -23.1843) -> (64.7796, -30.3261)
  line L489 (79.0632, -30.3261) -> (71.9214, -23.1843)
  line L490 (72.7699, -22.3358) -> (79.9117, -29.4775)
  line L491 (79.9117, -29.4775) -> (87.0535, -22.3358)
  line L492 (79.9117, -15.194) -> (72.7699, -22.3358)
  line L493 (87.0535, -22.3358) -> (79.9117, -15.194)
  line L494 (80.7602, -14.3455) -> (87.902, -21.4872)
  line L495 (87.902, -21.4872) -> (95.0438, -14.3455)
  line L496 (87.902, -7.2037) -> (80.7602, -14.3455)
  line L497 (95.0438, -14.3455) -> (87.902, -7.2037)
  line L498 (88.7505, -6.3552) -> (95.8923, -13.4969)
  line L499 (95.8923, -13.4969) -> (103.0341, -6.3552)
  line L500 (95.8923, 0.7866) -> (88.7505, -6.3552)